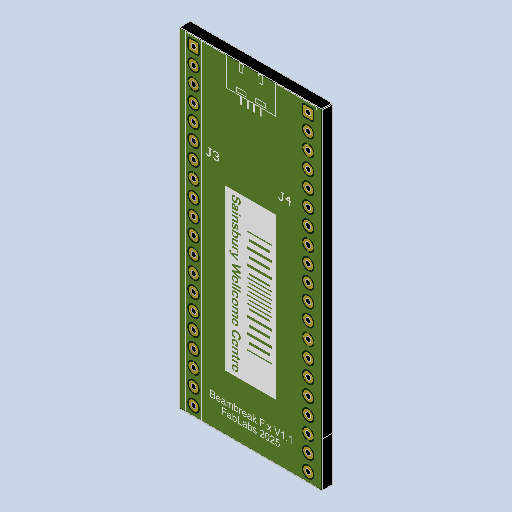
# Autodesk Inventor part: Beam_Break_-_Foraging_Feeder_Fix_BOARD
Saved by Autodesk Inventor 2025.4 (Build 294407000, 407)
## iProperties
Created: 2026-07-10
Part Number: Beam_Break_-_Foraging_Feeder_Fix_BOARD
Material: Generic
Document SubType Name: Modeling
Designer: Yuhsuan Chen
Density: 1 g/cm^3
Appearance: BoardColor
Author: Yuhsuan Chen
Autodesk Inventor part; units mm, degrees
ref_plane "YZ Plane" through (0, 0, 0) normal (1, 0, 0) x (0, 1, 0)
ref_plane "XZ Plane" through (0, 0, 0) normal (0, 1, 0) x (-1, 0, 0)
ref_plane "BoardFrontPlane" through (0, 0, 0) normal (0, 0, 1) x (1, 0, 0)
sketch "Sketch1" plane through (0, 0, 0) normal (0, 0, 1) x (1, 0, 0)
  line L0 (24.4, 24.9647) -> (24.4, 76.065)
  arc A0 (24.5, 76.165) -> (24.4, 76.065) centre (24.5, 76.065) ccw
  line L1 (24.5, 76.165) -> (46.5, 76.165)
  arc A1 (46.6, 76.065) -> (46.5, 76.165) centre (46.5, 76.065) ccw
  line L2 (46.6, 76.065) -> (46.6, 31.8679)
  line L3 (46.6, 31.8679) -> (46.6, 24.965)
  arc A2 (46.5, 24.865) -> (46.6, 24.965) centre (46.5, 24.965) ccw
  line L4 (46.5, 24.865) -> (24.4997, 24.865)
  arc A3 (24.4, 24.9647) -> (24.4997, 24.865) centre (24.4997, 24.9647) ccw
  constraints: 10 end point, 8 point on circle, 4 centre point
extrude "BoardOutline" add sketch "Sketch1" along normal blind 1.5954
sketch "img_Top" plane through (0, 0, 1.5954) normal (0, 0, 1) x (1, 0, 0)
  line L0 (24.4, 76.165) -> (46.6, 76.165) construction
  line L1 (46.6, 76.165) -> (46.6, 24.8561) construction
  line L2 (46.6, 24.8561) -> (24.4, 24.8561) construction
  line L3 (24.4, 24.8561) -> (24.4, 76.165) construction
  constraints: 2 other
decal "Decal_Top"
sketch "img_Bottom" plane through (0, 0, -1.5954) normal (0, 0, -1) x (1, 0, 0)
  line L0 (24.4, -24.865) -> (46.6, -24.865) construction
  line L1 (46.6, -24.865) -> (46.6, -76.1739) construction
  line L2 (46.6, -76.1739) -> (24.4, -76.1739) construction
  line L3 (24.4, -76.1739) -> (24.4, -24.865) construction
  constraints: 2 other
decal "Decal_Bottom"
sketch "Sketch4" plane through (0, 0, 1.5954) normal (0, 0, 1) x (1, 0, 0)
  point P0 (44.39, 51.77)
hole "J4-10" at (44.39, 51.77, 1.5954) direction (0, 0, -1) diameter 0.8 end through all
sketch "Sketch5" plane through (0, 0, 1.5954) normal (0, 0, 1) x (1, 0, 0)
  point P0 (44.39, 67.01)
hole "J4-4" at (44.39, 67.01, 1.5954) direction (0, 0, -1) diameter 0.8 end through all
sketch "Sketch6" plane through (0, 0, 1.5954) normal (0, 0, 1) x (1, 0, 0)
  point P0 (44.39, 72.09)
hole "J4-2" at (44.39, 72.09, 1.5954) direction (0, 0, -1) diameter 0.8 end through all
sketch "Sketch7" plane through (0, 0, 1.5954) normal (0, 0, 1) x (1, 0, 0)
  point P0 (44.39, 54.31)
hole "J4-9" at (44.39, 54.31, 1.5954) direction (0, 0, -1) diameter 0.8 end through all
sketch "Sketch8" plane through (0, 0, 1.5954) normal (0, 0, 1) x (1, 0, 0)
  point P0 (44.39, 64.47)
hole "J4-5" at (44.39, 64.47, 1.5954) direction (0, 0, -1) diameter 0.8 end through all
sketch "Sketch9" plane through (0, 0, 1.5954) normal (0, 0, 1) x (1, 0, 0)
  point P0 (44.39, 69.55)
hole "J4-3" at (44.39, 69.55, 1.5954) direction (0, 0, -1) diameter 0.8 end through all
sketch "Sketch10" plane through (0, 0, 1.5954) normal (0, 0, 1) x (1, 0, 0)
  point P0 (44.39, 74.63)
hole "J4-1" at (44.39, 74.63, 1.5954) direction (0, 0, -1) diameter 0.8 end through all
sketch "Sketch11" plane through (0, 0, 1.5954) normal (0, 0, 1) x (1, 0, 0)
  point P0 (44.39, 61.93)
hole "J4-6" at (44.39, 61.93, 1.5954) direction (0, 0, -1) diameter 0.8 end through all
sketch "Sketch12" plane through (0, 0, 1.5954) normal (0, 0, 1) x (1, 0, 0)
  point P0 (44.39, 59.39)
hole "J4-7" at (44.39, 59.39, 1.5954) direction (0, 0, -1) diameter 0.8 end through all
sketch "Sketch13" plane through (0, 0, 1.5954) normal (0, 0, 1) x (1, 0, 0)
  point P0 (44.39, 56.85)
hole "J4-8" at (44.39, 56.85, 1.5954) direction (0, 0, -1) diameter 0.8 end through all
sketch "Sketch14" plane through (0, 0, 1.5954) normal (0, 0, 1) x (1, 0, 0)
  point P0 (44.39, 31.45)
hole "J4-18" at (44.39, 31.45, 1.5954) direction (0, 0, -1) diameter 0.8 end through all
sketch "Sketch15" plane through (0, 0, 1.5954) normal (0, 0, 1) x (1, 0, 0)
  point P0 (44.39, 33.99)
hole "J4-17" at (44.39, 33.99, 1.5954) direction (0, 0, -1) diameter 0.8 end through all
sketch "Sketch16" plane through (0, 0, 1.5954) normal (0, 0, 1) x (1, 0, 0)
  point P0 (44.39, 36.53)
hole "J4-16" at (44.39, 36.53, 1.5954) direction (0, 0, -1) diameter 0.8 end through all
sketch "Sketch17" plane through (0, 0, 1.5954) normal (0, 0, 1) x (1, 0, 0)
  point P0 (44.39, 49.23)
hole "J4-11" at (44.39, 49.23, 1.5954) direction (0, 0, -1) diameter 0.8 end through all
sketch "Sketch18" plane through (0, 0, 1.5954) normal (0, 0, 1) x (1, 0, 0)
  point P0 (44.39, 44.15)
hole "J4-13" at (44.39, 44.15, 1.5954) direction (0, 0, -1) diameter 0.8 end through all
sketch "Sketch19" plane through (0, 0, 1.5954) normal (0, 0, 1) x (1, 0, 0)
  point P0 (44.39, 39.07)
hole "J4-15" at (44.39, 39.07, 1.5954) direction (0, 0, -1) diameter 0.8 end through all
sketch "Sketch20" plane through (0, 0, 1.5954) normal (0, 0, 1) x (1, 0, 0)
  point P0 (44.39, 28.91)
hole "J4-19" at (44.39, 28.91, 1.5954) direction (0, 0, -1) diameter 0.8 end through all
sketch "Sketch21" plane through (0, 0, 1.5954) normal (0, 0, 1) x (1, 0, 0)
  point P0 (44.39, 46.69)
hole "J4-12" at (44.39, 46.69, 1.5954) direction (0, 0, -1) diameter 0.8 end through all
sketch "Sketch22" plane through (0, 0, 1.5954) normal (0, 0, 1) x (1, 0, 0)
  point P0 (44.39, 41.61)
hole "J4-14" at (44.39, 41.61, 1.5954) direction (0, 0, -1) diameter 0.8 end through all
sketch "Sketch23" plane through (0, 0, 1.5954) normal (0, 0, 1) x (1, 0, 0)
  point P0 (44.39, 26.37)
hole "J4-20" at (44.39, 26.37, 1.5954) direction (0, 0, -1) diameter 0.8 end through all
sketch "Sketch24" plane through (0, 0, 1.5954) normal (0, 0, 1) x (1, 0, 0)
  point P0 (26.61, 51.77)
hole "J3-10" at (26.61, 51.77, 1.5954) direction (0, 0, -1) diameter 0.8 end through all
sketch "Sketch25" plane through (0, 0, 1.5954) normal (0, 0, 1) x (1, 0, 0)
  point P0 (26.61, 67.01)
hole "J3-4" at (26.61, 67.01, 1.5954) direction (0, 0, -1) diameter 0.8 end through all
sketch "Sketch26" plane through (0, 0, 1.5954) normal (0, 0, 1) x (1, 0, 0)
  point P0 (26.61, 72.09)
hole "J3-2" at (26.61, 72.09, 1.5954) direction (0, 0, -1) diameter 0.8 end through all
sketch "Sketch27" plane through (0, 0, 1.5954) normal (0, 0, 1) x (1, 0, 0)
  point P0 (26.61, 54.31)
hole "J3-9" at (26.61, 54.31, 1.5954) direction (0, 0, -1) diameter 0.8 end through all
sketch "Sketch28" plane through (0, 0, 1.5954) normal (0, 0, 1) x (1, 0, 0)
  point P0 (26.61, 64.47)
hole "J3-5" at (26.61, 64.47, 1.5954) direction (0, 0, -1) diameter 0.8 end through all
sketch "Sketch29" plane through (0, 0, 1.5954) normal (0, 0, 1) x (1, 0, 0)
  point P0 (26.61, 69.55)
hole "J3-3" at (26.61, 69.55, 1.5954) direction (0, 0, -1) diameter 0.8 end through all
sketch "Sketch30" plane through (0, 0, 1.5954) normal (0, 0, 1) x (1, 0, 0)
  point P0 (26.61, 74.63)
hole "J3-1" at (26.61, 74.63, 1.5954) direction (0, 0, -1) diameter 0.8 end through all
sketch "Sketch31" plane through (0, 0, 1.5954) normal (0, 0, 1) x (1, 0, 0)
  point P0 (26.61, 61.93)
hole "J3-6" at (26.61, 61.93, 1.5954) direction (0, 0, -1) diameter 0.8 end through all
sketch "Sketch32" plane through (0, 0, 1.5954) normal (0, 0, 1) x (1, 0, 0)
  point P0 (26.61, 59.39)
hole "J3-7" at (26.61, 59.39, 1.5954) direction (0, 0, -1) diameter 0.8 end through all
sketch "Sketch33" plane through (0, 0, 1.5954) normal (0, 0, 1) x (1, 0, 0)
  point P0 (26.61, 56.85)
hole "J3-8" at (26.61, 56.85, 1.5954) direction (0, 0, -1) diameter 0.8 end through all
sketch "Sketch34" plane through (0, 0, 1.5954) normal (0, 0, 1) x (1, 0, 0)
  point P0 (26.61, 31.45)
hole "J3-18" at (26.61, 31.45, 1.5954) direction (0, 0, -1) diameter 0.8 end through all
sketch "Sketch35" plane through (0, 0, 1.5954) normal (0, 0, 1) x (1, 0, 0)
  point P0 (26.61, 33.99)
hole "J3-17" at (26.61, 33.99, 1.5954) direction (0, 0, -1) diameter 0.8 end through all
sketch "Sketch36" plane through (0, 0, 1.5954) normal (0, 0, 1) x (1, 0, 0)
  point P0 (26.61, 36.53)
hole "J3-16" at (26.61, 36.53, 1.5954) direction (0, 0, -1) diameter 0.8 end through all
sketch "Sketch37" plane through (0, 0, 1.5954) normal (0, 0, 1) x (1, 0, 0)
  point P0 (26.61, 49.23)
hole "J3-11" at (26.61, 49.23, 1.5954) direction (0, 0, -1) diameter 0.8 end through all
sketch "Sketch38" plane through (0, 0, 1.5954) normal (0, 0, 1) x (1, 0, 0)
  point P0 (26.61, 44.15)
hole "J3-13" at (26.61, 44.15, 1.5954) direction (0, 0, -1) diameter 0.8 end through all
sketch "Sketch39" plane through (0, 0, 1.5954) normal (0, 0, 1) x (1, 0, 0)
  point P0 (26.61, 39.07)
hole "J3-15" at (26.61, 39.07, 1.5954) direction (0, 0, -1) diameter 0.8 end through all
sketch "Sketch40" plane through (0, 0, 1.5954) normal (0, 0, 1) x (1, 0, 0)
  point P0 (26.61, 28.91)
hole "J3-19" at (26.61, 28.91, 1.5954) direction (0, 0, -1) diameter 0.8 end through all
sketch "Sketch41" plane through (0, 0, 1.5954) normal (0, 0, 1) x (1, 0, 0)
  point P0 (26.61, 46.69)
hole "J3-12" at (26.61, 46.69, 1.5954) direction (0, 0, -1) diameter 0.8 end through all
sketch "Sketch42" plane through (0, 0, 1.5954) normal (0, 0, 1) x (1, 0, 0)
  point P0 (26.61, 41.61)
hole "J3-14" at (26.61, 41.61, 1.5954) direction (0, 0, -1) diameter 0.8 end through all
sketch "Sketch43" plane through (0, 0, 1.5954) normal (0, 0, 1) x (1, 0, 0)
  point P0 (26.61, 26.37)
hole "J3-20" at (26.61, 26.37, 1.5954) direction (0, 0, -1) diameter 0.8 end through all
body "Solid1"
